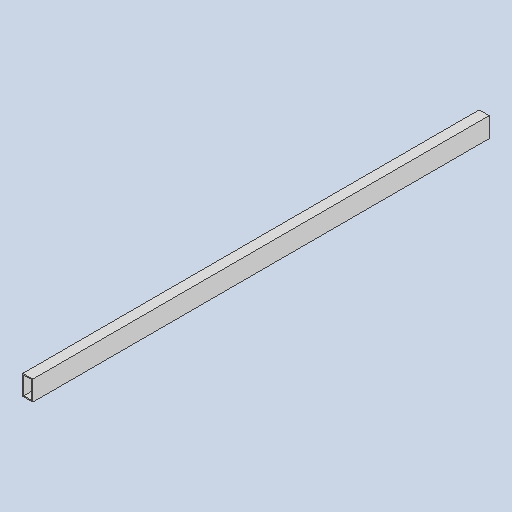
# Autodesk Inventor part: RDS-2002 Tube 40x20 L916
Saved by Autodesk Inventor 2026.2 (Build 302298000, 298)
## iProperties
Created: 2026-10-12
Part Number: RDS-2002 Tube 40x20 L916
Material: Generic
Description: Tube 40x20x2 AISI 304, L=916
Document SubType Name: Modeling
Designer: admin
Stock Number: Труба 40х20х2 L916
Density: 1 g/cm^3
Appearance: Default
Author: admin
Autodesk Inventor part; units mm, degrees
ref_plane "YZ Plane" through (0, 0, 0) normal (1, 0, 0) x (0, 1, 0)
ref_plane "XZ Plane" through (0, 0, 0) normal (0, 1, 0) x (-1, 0, 0)
ref_plane "XY Plane" through (0, 0, 0) normal (0, 0, 1) x (1, 0, 0)
sketch "Sketch1" plane through (0, 0, 0) normal (0, 0, 1) x (1, 0, 0)
  line L0 (-10, -20) -> (10, -20)
  line L1 (10, -20) -> (10, 20)
  line L2 (10, 20) -> (-10, 20)
  line L3 (-10, 20) -> (-10, -20)
  line L4 (-8, -18) -> (8, -18)
  line L5 (8, -18) -> (8, 18)
  line L6 (8, 18) -> (-8, 18)
  line L7 (-8, 18) -> (-8, -18)
  constraints: 16 end point, 4 parallel, 2 horizontal, 2 perpendicular
extrude "Extrusion1" add sketch "Sketch1" along normal blind 916
equation "\"d0\" = Tube2002_Length"
equation "\"Tube2002_Length\" = 916"
body "Solid1"
